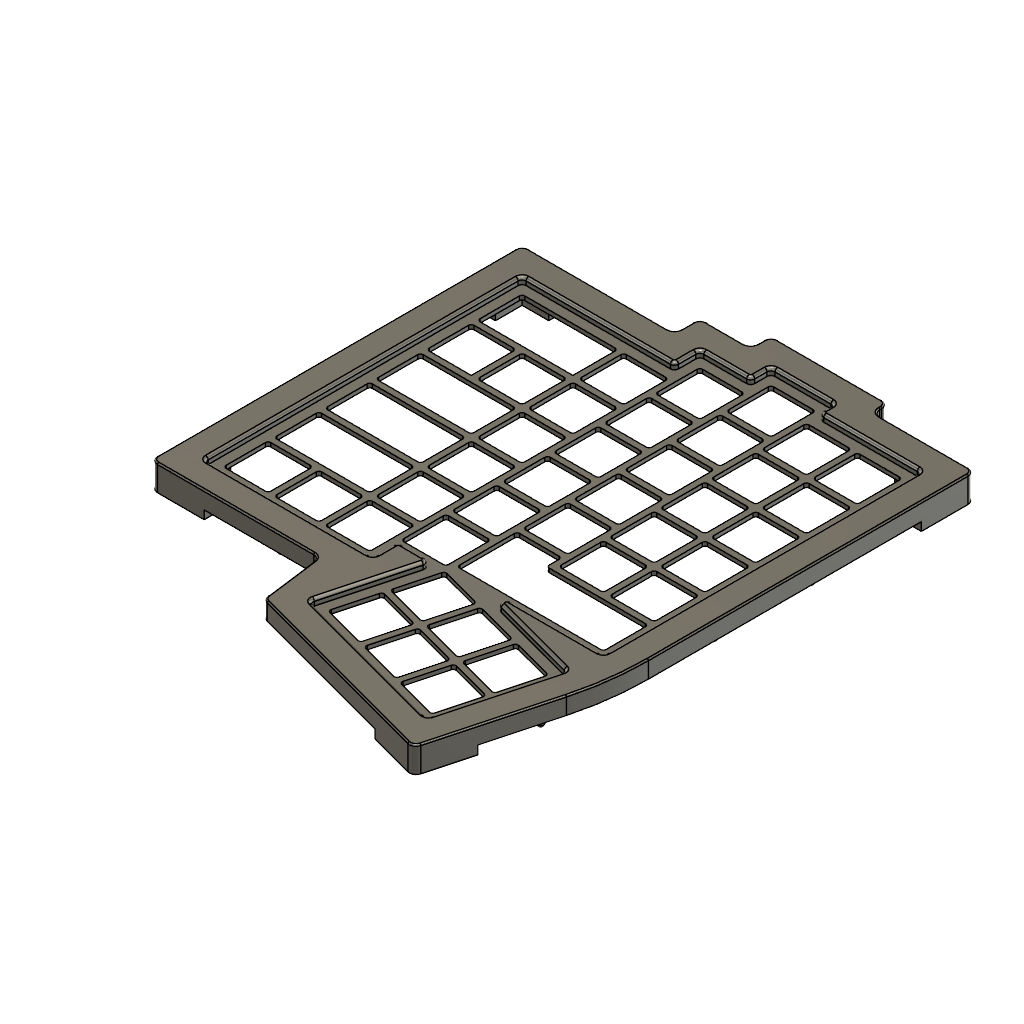
Case Top (Castor) (Autodesk Fusion 360 archive; units mm, degrees)
design "Case Top (Castor)" references "_Globals"
part number: 2026-10-17-17-44-59-793
Autodesk Fusion 360 part; units mm, degrees
(part 1 of 3)
derive "ExternalDerived1"
sketch "Sketch1" plane through (0, 0, 0) normal (0, 1, 0) x (1, 0, 0)
  line L0 (66.675, 57.15) -> (-66.675, 57.15) construction
  line L1 (-66.675, 57.15) -> (-66.675, -57.15) construction
  line L2 (-66.675, -57.15) -> (66.675, -57.15) construction
  line L3 (66.675, -57.15) -> (66.675, 57.15) construction
  line L4 (66.675, 57.15) -> (-66.675, -57.15) construction
  line L5 (-66.675, 57.15) -> (66.675, -57.15) construction
  line L6 (-66.675, 57.15) -> (-9.525, 57.15) construction
  line L7 (-9.525, 57.15) -> (-9.525, 66.675) construction
  line L8 (-9.525, 66.675) -> (9.525, 66.675) construction
  line L9 (9.525, 66.675) -> (9.525, 74.295) construction
  line L10 (9.525, 74.295) -> (28.575, 74.295) construction
  line L11 (28.575, 74.295) -> (28.575, 68.58) construction
  line L12 (28.575, 68.58) -> (66.675, 68.58) construction
  line L13 (66.675, 68.58) -> (66.675, 57.15) construction
  line L14 (-66.675, -57.15) -> (-9.525, -57.15) construction
  line L15 (-9.525, -57.15) -> (-9.525, -47.625) construction
  line L16 (-9.525, -47.625) -> (9.525, -47.625) construction
  line L17 (9.525, -47.625) -> (9.525, -45.72) construction
  line L18 (9.525, -45.72) -> (66.675, -45.72) construction
  line L19 (-66.675, -57.15) -> (-69.15, -57.15) construction
  line L20 (-69.15, -57.15) -> (-69.15, -59.625) construction
  line L21 (-66.675, 57.15) -> (-66.675, 59.625) construction
  line L22 (-66.675, 59.625) -> (-69.15, 59.625) construction
  line L23 (-9.525, 57.15) -> (-12, 57.15) construction
  line L24 (-12, 57.15) -> (-12, 59.625) construction
  line L25 (-9.525, 66.675) -> (-12, 66.675) construction
  line L26 (-12, 66.675) -> (-12, 69.15) construction
  line L27 (9.525, 66.675) -> (7.05, 66.675) construction
  line L28 (7.05, 66.675) -> (7.05, 69.15) construction
  line L29 (9.525, 74.295) -> (7.05, 74.295) construction
  line L30 (7.05, 74.295) -> (7.05, 76.77) construction
  line L31 (28.575, 74.295) -> (31.05, 74.295) construction
  line L32 (31.05, 74.295) -> (31.05, 76.77) construction
  line L33 (28.575, 68.58) -> (31.05, 68.58) construction
  line L34 (31.05, 68.58) -> (31.05, 71.055) construction
  line L35 (66.675, 68.58) -> (69.15, 68.58) construction
  line L36 (69.15, 68.58) -> (69.15, 71.055) construction
  line L37 (66.675, -45.72) -> (69.15, -45.72) construction
  line L38 (69.15, -45.72) -> (69.15, -48.195) construction
  line L39 (-9.525, -57.15) -> (-7.05, -57.15) construction
  line L40 (-7.05, -57.15) -> (-7.05, -59.625) construction
  line L41 (9.525, -47.625) -> (9.525, -47.73) construction
  line L42 (9.525, -47.73) -> (9.59, -47.73) construction
  line L43 (9.59, -47.73) -> (9.7259, -47.2229) construction
  line L44 (9.7259, -47.2229) -> (9.2188, -47.087) construction
  line L45 (9.2188, -47.087) -> (64.4214, -61.8785) construction
  line L46 (64.4214, -61.8785) -> (54.5604, -98.6803) construction
  line L47 (54.5604, -98.6803) -> (-0.6422, -83.8888) construction
  line L48 (-0.6422, -83.8888) -> (9.2188, -47.087) construction
  line L49 (-0.6422, -83.8888) -> (-1.2828, -86.2794) construction
  line L50 (-1.2828, -86.2794) -> (-3.6735, -85.6389) construction
  line L51 (54.5604, -98.6803) -> (53.9198, -101.071) construction
  line L52 (53.9198, -101.071) -> (56.3105, -101.7115) construction
  line L53 (64.4214, -61.8785) -> (65.062, -59.4879) construction
  line L54 (65.062, -59.4879) -> (67.4527, -60.1284) construction
  line L55 (-69.15, 59.625) -> (-12, 59.625)
  line L56 (-12, 59.625) -> (-12, 69.15)
  line L57 (-12, 69.15) -> (7.05, 69.15)
  line L58 (7.05, 69.15) -> (7.05, 76.77)
  line L59 (7.05, 76.77) -> (31.05, 76.77)
  line L60 (31.05, 76.77) -> (31.05, 71.055)
  line L61 (31.05, 71.055) -> (69.15, 71.055)
  line L62 (69.15, 71.055) -> (69.15, -48.195)
  line L63 (67.4527, -60.1284) -> (69.15, -48.195)
  line L64 (67.4527, -60.1284) -> (56.3105, -101.7115)
  line L65 (56.3105, -101.7115) -> (-3.6735, -85.6389)
  line L66 (-7.05, -59.625) -> (-3.6735, -85.6389)
  line L67 (-7.05, -59.625) -> (-69.15, -59.625)
  line L68 (-69.15, -59.625) -> (-69.15, 59.625)
  line L69 (-22, 79.15) -> (-2.95, 79.15)
  line L70 (-2.95, 79.15) -> (-2.95, 86.77)
  line L71 (-2.95, 86.77) -> (41.05, 86.77)
  line L72 (41.05, 86.77) -> (41.05, 81.055)
  line L73 (41.05, 81.055) -> (79.15, 81.055)
  line L74 (79.15, 81.055) -> (79.15, -48.9026)
  line L75 (77.2681, -62.1339) -> (79.15, -48.9026)
  line L76 (77.2681, -62.1339) -> (63.3816, -113.959)
  line L77 (63.3816, -113.959) -> (-12.7285, -93.5653)
  line L78 (-15.8359, -69.625) -> (-12.7285, -93.5653)
  line L79 (-15.8359, -69.625) -> (-79.15, -69.625)
  line L80 (-79.15, -69.625) -> (-79.15, 69.625)
  line L81 (-79.15, 69.625) -> (-22, 69.625)
  line L82 (-22, 69.625) -> (-22, 79.15)
  dimension "d42" = 133.35
  dimension "d43" = 114.3
  dimension "d44" = 57.15
  dimension "d45" = 9.525
  dimension "d46" = 19.05
  dimension "d47" = 7.62
  dimension "d48" = 19.05
  dimension "d49" = 5.715
  dimension "d50" = 38.1
  dimension "d51" = 57.15
  dimension "d52" = 9.525
  dimension "d53" = 19.05
  dimension "d54" = 1.905
  dimension "d55" = 2.475
  dimension "d56" = 2.475
  dimension "d57" = 2.475
  dimension "d58" = 2.475
  dimension "d59" = 2.475
  dimension "d60" = 2.475
  dimension "d61" = 2.475
  dimension "d62" = 2.475
  dimension "d63" = 2.475
  dimension "d64" = 2.475
  dimension "d65" = 2.475
  dimension "d66" = 2.475
  dimension "d67" = 2.475
  dimension "d68" = 2.475
  dimension "d69" = 2.475
  dimension "d70" = 2.475
  dimension "d71" = 2.475
  dimension "d72" = 2.475
  dimension "d73" = 2.475
  dimension "d74" = 2.475
  dimension "d75" = 2.475
  dimension "d76" = 2.475
  dimension "d77" = 0.105
  dimension "d78" = 0.065
  dimension "d79" = 0.525
  dimension "d80" = 0.525
  dimension "d81" = 57.15
  dimension "d82" = 38.1
  dimension "d83" = 2.475
  dimension "d84" = 2.475
  dimension "d85" = 2.475
  dimension "d86" = 2.475
  dimension "d87" = 2.475
  dimension "d88" = 2.475
  constraint horizontal L0
  constraint perpendicular L0 L1
  constraint parallel L0 L2
  constraint parallel L1 L3
  constraint coincident L4 origin
  constraint coincident L5 origin
  constraint perpendicular L1 L6
  constraint perpendicular L0 L7
  constraint perpendicular L7 L8
  constraint perpendicular L8 L9
  constraint perpendicular L9 L10
  constraint perpendicular L8 L11
  constraint perpendicular L9 L12
  constraint perpendicular L1 L14
  constraint perpendicular L2 L15
  constraint perpendicular L15 L16
  constraint perpendicular L2 L17
  constraint coincident L3 L18.end
  constraint perpendicular L3 L18
  constraint perpendicular L1 L19
  constraint perpendicular L19 L20
  constraint perpendicular L6 L21
  constraint perpendicular L21 L22
  constraint perpendicular L7 L23
  constraint perpendicular L23 L24
  constraint perpendicular L7 L25
  constraint perpendicular L25 L26
  constraint perpendicular L9 L27
  constraint perpendicular L27 L28
  constraint perpendicular L9 L29
  constraint perpendicular L10 L30
  constraint perpendicular L11 L31
  constraint perpendicular L10 L32
  constraint perpendicular L11 L33
  constraint perpendicular L33 L34
  constraint perpendicular L13 L35
  constraint perpendicular L12 L36
  constraint perpendicular L3 L37
  constraint perpendicular L18 L38
  constraint perpendicular L15 L39
  constraint perpendicular L39 L40
  constraint perpendicular L16 L41
  constraint perpendicular L17 L42
  constraint parallel L46 L48
  constraint parallel L45 L47
  constraint perpendicular L47 L48
  constraint collinear L44 L45
  constraint perpendicular L43 L44
  constraint perpendicular L47 L49
  constraint perpendicular L48 L50
  constraint perpendicular L47 L51
  constraint perpendicular L51 L52
  constraint perpendicular L45 L53
  constraint perpendicular L53 L54
  measures "d42" distance of L1.end L2.end
  measures "d43" distance of L0.end L1.end
  measures "d44" distance of L0.end L6.end
  measures "d45" distance of L6.end L7.end
  measures "d46" distance of L7.end L8.end
  measures "d47" distance of L8.end L9.end
  measures "d48" distance of L9.end L10.end
  measures "d49" distance of L10.end L11.end
  measures "d50" distance of L11.end L12.end
  measures "d51" distance of L1.end L14.end
  measures "d52" distance of L14.end L15.end
  measures "d53" distance of L15.end L16.end
  measures "d54" distance of L16.end L17.end
  measures "d55" distance of L1.end L19.end
  measures "d56" distance of L19.end L20.end
  measures "d57" distance of L0.end L21.end
  measures "d58" distance of L21.end L22.end
  measures "d59" distance of L6.end L23.end
  measures "d60" distance of L23.end L24.end
  measures "d61" distance of L7.end L25.end
  measures "d62" distance of L25.end L26.end
  measures "d63" distance of L8.end L27.end
  measures "d64" distance of L27.end L28.end
  measures "d65" distance of L9.end L29.end
  measures "d66" distance of L29.end L30.end
  measures "d67" distance of L10.end L31.end
  measures "d68" distance of L31.end L32.end
  measures "d69" distance of L11.end L33.end
  measures "d70" distance of L33.end L34.end
  measures "d71" distance of L12.end L35.end
  measures "d72" distance of L35.end L36.end
  measures "d73" distance of L18.end L37.end
  measures "d74" distance of L37.end L38.end
  measures "d75" distance of L14.end L39.end
  measures "d76" distance of L39.end L40.end
  measures "d77" distance of L16.end L41.end
  measures "d78" distance of L41.end L42.end
  measures "d79" distance of L42.end L43.end
  measures "d80" distance of L43.end L44.end
  measures "d81" distance of L44.end L45.end
  measures "d82" distance of L44.end L47.end
  measures "d83" distance of L47.end L49.end
  measures "d84" distance of L49.end L50.end
  measures "d85" distance of L46.end L51.end
  measures "d86" distance of L51.end L52.end
  measures "d87" distance of L45.end L53.end
  measures "d88" distance of L53.end L54.end
extrude "Extrude1" add sketch "Sketch1" against normal blind 1.5 contours L55 L56 L57 L58 L59 L60 L61 L62 L63 L64 L65 L66 L67 L68
extrude "Extrude2" add sketch "Sketch1" against normal blind 4
sketch "Sketch2" plane through (0, 0, 0) normal (0, 1, 0) x (-1, 0, 0)
  line L0 (15.8359, 69.625) -> (12.7285, 93.5653)
  line L1 (12.7285, 93.5653) -> (-63.3816, 113.959)
  line L2 (-63.3816, 113.959) -> (-77.2681, 62.1339)
  line L3 (-77.2681, 62.1339) -> (-79.15, 48.9026)
  line L4 (-79.15, 48.9026) -> (-79.15, -81.055)
  line L5 (-79.15, -81.055) -> (-41.05, -81.055)
  line L6 (-41.05, -81.055) -> (-41.05, -86.77)
  line L7 (-41.05, -86.77) -> (2.95, -86.77)
  line L8 (2.95, -86.77) -> (2.95, -79.15)
  line L9 (2.95, -79.15) -> (22, -79.15)
  line L10 (22, -79.15) -> (22, -69.625)
  line L11 (22, -69.625) -> (79.15, -69.625)
  line L12 (79.15, -69.625) -> (79.15, 69.625)
  line L13 (79.15, 69.625) -> (15.8359, 69.625)
  line L14 (79.15, -69.625) -> (79.15, -57.15) construction
  line L15 (79.15, -57.15) -> (66.675, -57.15) construction
  line L16 (66.675, -57.15) -> (47.625, -57.15) construction
  line L17 (47.625, -57.15) -> (9.525, -57.15) construction
  line L18 (9.525, -57.15) -> (9.525, -66.675) construction
  line L19 (9.525, -66.675) -> (-9.525, -66.675) construction
  line L20 (-9.525, -66.675) -> (-9.525, -74.295) construction
  line L21 (-9.525, -74.295) -> (-28.575, -74.295) construction
  line L22 (-28.575, -74.295) -> (-28.575, -68.58) construction
  line L23 (-28.575, -68.58) -> (-47.625, -68.58) construction
  line L24 (-47.625, -68.58) -> (-66.675, -68.58) construction
  line L25 (-66.675, -68.58) -> (-66.675, 26.67) construction
  line L26 (-66.675, 26.67) -> (-28.575, 26.67) construction
  line L27 (-28.575, 26.67) -> (-28.575, -68.58) construction
  line L28 (-47.625, -68.58) -> (-47.625, -49.53) construction
  line L29 (-47.625, -49.53) -> (-28.575, -49.53) construction
  line L30 (-28.575, -68.58) -> (-47.625, -49.53) construction
  line L31 (-47.625, -68.58) -> (-28.575, -49.53) construction
  line L32 (-9.525, -66.675) -> (-9.525, -55.245) construction
  line L33 (-9.525, -55.245) -> (-28.575, -55.245) construction
  line L34 (9.525, -57.15) -> (9.525, -47.625) construction
  line L35 (9.525, -47.625) -> (-9.525, -47.625) construction
  line L36 (-9.525, -55.245) -> (-9.525, 20.955) construction
  line L37 (-9.525, 20.955) -> (-28.575, 20.955) construction
  line L38 (9.525, -47.625) -> (9.525, 47.625) construction
  line L39 (9.525, 47.625) -> (-9.525, 47.625) construction
  line L40 (-9.525, 47.625) -> (-9.525, 20.955) construction
  line L41 (66.675, -57.15) -> (66.675, -38.1) construction
  line L42 (66.675, -38.1) -> (66.675, -19.05) construction
  line L43 (66.675, -19.05) -> (66.675, 38.1) construction
  line L44 (66.675, 38.1) -> (66.675, 57.15) construction
  line L45 (66.675, 57.15) -> (47.625, 57.15) construction
  line L46 (47.625, 57.15) -> (9.525, 57.15) construction
  line L47 (9.525, 57.15) -> (9.525, 47.625) construction
  line L48 (66.675, 38.1) -> (47.625, 38.1) construction
  line L49 (47.625, 38.1) -> (9.525, 38.1) construction
  line L50 (47.625, 38.1) -> (47.625, 57.15) construction
  line L51 (28.575, -57.15) -> (28.575, -38.1) construction
  line L52 (28.575, -38.1) -> (47.625, -38.1) construction
  line L53 (47.625, -38.1) -> (66.675, -38.1) construction
  line L54 (47.625, -38.1) -> (47.625, -19.05) construction
  line L55 (47.625, -19.05) -> (66.675, -19.05) construction
  line L56 (28.575, -38.1) -> (28.575, 38.1) construction
  line L57 (28.575, -38.1) -> (9.525, -38.1) construction
  line L58 (47.625, -19.05) -> (28.575, -19.05) construction
  line L59 (66.675, -57.15) -> (28.575, -38.1) construction
  line L60 (28.575, -57.15) -> (66.675, -38.1) construction
  line L61 (66.675, -38.1) -> (47.625, -19.05) construction
  line L62 (47.625, -38.1) -> (66.675, -19.05) construction
  line L63 (9.525, -66.675) -> (-9.525, -47.625) construction
  line L64 (-9.525, -66.675) -> (9.525, -47.625) construction
  line L65 (-9.525, -74.295) -> (-28.575, -55.245) construction
  line L66 (-28.575, -74.295) -> (-9.525, -55.245) construction
  line L67 (-66.675, 26.67) -> (-66.675, 45.72) construction
  line L68 (-66.675, 45.72) -> (-9.525, 45.72) construction
  line L69 (-9.525, 45.72) -> (-66.675, 26.67) construction
  line L70 (-28.575, 26.67) -> (-9.525, 26.67) construction
  line L71 (-66.675, 45.72) -> (-9.525, 26.67) construction
  line L72 (66.675, 38.1) -> (47.625, 57.15) construction
  line L73 (47.625, 38.1) -> (66.675, 57.15) construction
  line L74 (-9.525, 47.625) -> (-9.525, 47.73) construction
  line L75 (-9.525, 47.73) -> (-9.59, 47.73) construction
  line L76 (-9.59, 47.73) -> (-9.7259, 47.2229) construction
  line L77 (-9.7259, 47.2229) -> (-9.2188, 47.087) construction
  line L78 (-9.2188, 47.087) -> (-4.2883, 65.4879) construction
  line L79 (-4.2883, 65.4879) -> (-22.6892, 70.4184) construction
  line L80 (-22.6892, 70.4184) -> (-27.6197, 52.0175) construction
  line L81 (-27.6197, 52.0175) -> (-9.2188, 47.087) construction
  line L82 (-9.2188, 47.087) -> (-22.6892, 70.4184) construction
  line L83 (-27.6197, 52.0175) -> (-4.2883, 65.4879) construction
  line L84 (-4.2883, 65.4879) -> (0.6422, 83.8888) construction
  line L85 (0.6422, 83.8888) -> (-54.5604, 98.6803) construction
  line L86 (-54.5604, 98.6803) -> (-64.4214, 61.8785) construction
  line L87 (-64.4214, 61.8785) -> (-27.6197, 52.0175) construction
  line L88 (-26.206, 52.8216) -> (-10.0229, 48.5007)
  line L89 (-10.0229, 48.5007) -> (-5.702, 64.6838)
  line L90 (-5.702, 64.6838) -> (-21.885, 69.0047)
  line L91 (-21.885, 69.0047) -> (-26.206, 52.8216)
  line L92 (-26.206, 52.8216) -> (-5.702, 64.6838) construction
  line L93 (-10.0229, 48.5007) -> (-21.885, 69.0047) construction
  line L94 (-28.4238, 53.4312) -> (-24.1028, 69.6143)
  line L95 (-24.1028, 69.6143) -> (-40.2859, 73.9352)
  line L96 (-40.2859, 73.9352) -> (-44.6069, 57.7521)
  line L97 (-44.6069, 57.7521) -> (-28.4238, 53.4312)
  line L98 (-46.8247, 58.3617) -> (-42.5037, 74.5448)
  line L99 (-42.5037, 74.5448) -> (-58.6868, 78.8657)
  line L100 (-58.6868, 78.8657) -> (-63.0077, 62.6826)
  line L101 (-63.0077, 62.6826) -> (-46.8247, 58.3617)
  line L102 (-5.0924, 66.9016) -> (-0.7715, 83.0847)
  line L103 (-0.7715, 83.0847) -> (-16.9545, 87.4056)
  line L104 (-16.9545, 87.4056) -> (-21.2755, 71.2225)
  line L105 (-21.2755, 71.2225) -> (-5.0924, 66.9016)
  line L106 (-23.4933, 71.8321) -> (-19.1723, 88.0152)
  line L107 (-19.1723, 88.0152) -> (-35.3554, 92.3361)
  line L108 (-35.3554, 92.3361) -> (-39.6764, 76.153)
  line L109 (-39.6764, 76.153) -> (-23.4933, 71.8321)
  line L110 (-41.8942, 76.7626) -> (-37.5732, 92.9457)
  line L111 (-37.5732, 92.9457) -> (-53.7563, 97.2666)
  line L112 (-53.7563, 97.2666) -> (-58.0772, 81.0835)
  line L113 (-58.0772, 81.0835) -> (-41.8942, 76.7626)
  line L114 (48.775, 39.25) -> (65.525, 39.25)
  line L115 (65.525, 39.25) -> (65.525, 56)
  line L116 (65.525, 56) -> (48.775, 56)
  line L117 (48.775, 56) -> (48.775, 39.25)
  line L118 (48.775, 39.25) -> (65.525, 56) construction
  line L119 (65.525, 39.25) -> (48.775, 56) construction
  line L120 (48.775, -36.95) -> (65.525, -36.95)
  line L121 (65.525, -36.95) -> (65.525, -20.2)
  line L122 (65.525, -20.2) -> (48.775, -20.2)
  line L123 (48.775, -20.2) -> (48.775, -36.95)
  line L124 (48.775, -36.95) -> (65.525, -20.2) construction
  line L125 (65.525, -36.95) -> (48.775, -20.2) construction
  line L126 (-8.375, -65.525) -> (8.375, -65.525)
  line L127 (8.375, -65.525) -> (8.375, -48.775)
  line L128 (8.375, -48.775) -> (-8.375, -48.775)
  line L129 (-8.375, -48.775) -> (-8.375, -65.525)
  line L130 (-8.375, -65.525) -> (8.375, -48.775) construction
  line L131 (8.375, -65.525) -> (-8.375, -48.775) construction
  line L132 (-27.425, -73.145) -> (-10.675, -73.145)
  line L133 (-10.675, -73.145) -> (-10.675, -56.395)
  line L134 (-10.675, -56.395) -> (-27.425, -56.395)
  line L135 (-27.425, -56.395) -> (-27.425, -73.145)
  line L136 (-27.425, -73.145) -> (-10.675, -56.395) construction
  line L137 (-10.675, -73.145) -> (-27.425, -56.395) construction
  line L138 (-46.475, -67.43) -> (-29.725, -67.43)
  line L139 (-29.725, -67.43) -> (-29.725, -50.68)
  line L140 (-29.725, -50.68) -> (-46.475, -50.68)
  line L141 (-46.475, -50.68) -> (-46.475, -67.43)
  line L142 (-46.475, -67.43) -> (-29.725, -50.68) construction
  line L143 (-29.725, -67.43) -> (-46.475, -50.68) construction
  line L144 (29.725, -56) -> (65.525, -56)
  line L145 (65.525, -56) -> (65.525, -39.25)
  line L146 (65.525, -39.25) -> (29.725, -39.25)
  line L147 (29.725, -39.25) -> (29.725, -56)
  line L148 (29.725, -56) -> (65.525, -39.25) construction
  line L149 (65.525, -56) -> (29.725, -39.25) construction
  line L150 (-65.525, 27.82) -> (-10.675, 27.82)
  line L151 (-10.675, 27.82) -> (-10.675, 44.57)
  line L152 (-10.675, 44.57) -> (-65.525, 44.57)
  line L153 (-65.525, 44.57) -> (-65.525, 27.82)
  line L154 (-65.525, 27.82) -> (-10.675, 44.57) construction
  line L155 (-10.675, 27.82) -> (-65.525, 44.57) construction
  line L156 (-10.675, 27.82) -> (-27.425, 27.82)
  line L157 (-27.425, 27.82) -> (-27.425, 22.105)
  line L158 (-27.425, 22.105) -> (-10.675, 22.105)
  line L159 (-10.675, 22.105) -> (-10.675, 27.82)
  line L160 (46.475, 39.25) -> (46.475, 56)
  line L161 (46.475, 56) -> (29.725, 56)
  line L162 (29.725, 56) -> (29.725, 39.25)
  line L163 (29.725, 39.25) -> (46.475, 39.25)
  line L164 (27.425, 39.25) -> (27.425, 56)
  line L165 (27.425, 56) -> (10.675, 56)
  line L166 (10.675, 56) -> (10.675, 39.25)
  line L167 (10.675, 39.25) -> (27.425, 39.25)
  line L168 (46.475, -36.95) -> (46.475, -20.2)
  line L169 (46.475, -20.2) -> (29.725, -20.2)
  line L170 (29.725, -20.2) -> (29.725, -36.95)
  line L171 (29.725, -36.95) -> (46.475, -36.95)
  line L172 (28.575, -57.15) -> (9.525, -38.1) construction
  line L173 (28.575, -38.1) -> (9.525, -57.15) construction
  line L174 (10.675, -56) -> (27.425, -56)
  line L175 (27.425, -56) -> (27.425, -39.25)
  line L176 (27.425, -39.25) -> (10.675, -39.25)
  line L177 (10.675, -39.25) -> (10.675, -56)
  line L178 (10.675, -56) -> (27.425, -39.25) construction
  line L179 (27.425, -56) -> (10.675, -39.25) construction
  line L180 (10.675, -36.95) -> (27.425, -36.95)
  line L181 (27.425, -36.95) -> (27.425, -20.2)
  line L182 (27.425, -20.2) -> (10.675, -20.2)
  line L183 (10.675, -20.2) -> (10.675, -36.95)
  line L184 (10.675, -17.9) -> (27.425, -17.9)
  line L185 (27.425, -17.9) -> (27.425, -1.15)
  line L186 (27.425, -1.15) -> (10.675, -1.15)
  line L187 (10.675, -1.15) -> (10.675, -17.9)
  line L188 (10.675, 1.15) -> (27.425, 1.15)
  line L189 (27.425, 1.15) -> (27.425, 17.9)
  line L190 (27.425, 17.9) -> (10.675, 17.9)
  line L191 (10.675, 17.9) -> (10.675, 1.15)
  line L192 (10.675, 20.2) -> (27.425, 20.2)
  line L193 (27.425, 20.2) -> (27.425, 36.95)
  line L194 (27.425, 36.95) -> (10.675, 36.95)
  line L195 (10.675, 36.95) -> (10.675, 20.2)
  line L196 (8.375, -46.475) -> (8.375, -29.725)
  line L197 (8.375, -29.725) -> (-8.375, -29.725)
  line L198 (-8.375, -29.725) -> (-8.375, -46.475)
  line L199 (-8.375, -46.475) -> (8.375, -46.475)
  line L200 (8.375, -27.425) -> (8.375, -10.675)
  line L201 (8.375, -10.675) -> (-8.375, -10.675)
  line L202 (-8.375, -10.675) -> (-8.375, -27.425)
  line L203 (-8.375, -27.425) -> (8.375, -27.425)
  line L204 (8.375, -8.375) -> (8.375, 8.375)
  line L205 (8.375, 8.375) -> (-8.375, 8.375)
  line L206 (-8.375, 8.375) -> (-8.375, -8.375)
  line L207 (-8.375, -8.375) -> (8.375, -8.375)
  line L208 (8.375, 10.675) -> (8.375, 27.425)
  line L209 (8.375, 27.425) -> (-8.375, 27.425)
  line L210 (-8.375, 27.425) -> (-8.375, 10.675)
  line L211 (-8.375, 10.675) -> (8.375, 10.675)
  line L212 (8.375, 29.725) -> (8.375, 46.475)
  line L213 (8.375, 46.475) -> (-8.375, 46.475)
  line L214 (-8.375, 46.475) -> (-8.375, 29.725)
  line L215 (-8.375, 29.725) -> (8.375, 29.725)
  line L216 (-10.675, -54.095) -> (-10.675, -37.345)
  line L217 (-10.675, -37.345) -> (-27.425, -37.345)
  line L218 (-27.425, -37.345) -> (-27.425, -54.095)
  line L219 (-27.425, -54.095) -> (-10.675, -54.095)
  line L220 (-10.675, -35.045) -> (-10.675, -18.295)
  line L221 (-10.675, -18.295) -> (-27.425, -18.295)
  line L222 (-27.425, -18.295) -> (-27.425, -35.045)
  line L223 (-27.425, -35.045) -> (-10.675, -35.045)
  line L224 (-10.675, -15.995) -> (-10.675, 0.755)
  line L225 (-10.675, 0.755) -> (-27.425, 0.755)
  line L226 (-27.425, 0.755) -> (-27.425, -15.995)
  line L227 (-27.425, -15.995) -> (-10.675, -15.995)
  line L228 (-10.675, 3.055) -> (-10.675, 19.805)
  line L229 (-10.675, 19.805) -> (-27.425, 19.805)
  line L230 (-27.425, 19.805) -> (-27.425, 3.055)
  line L231 (-27.425, 3.055) -> (-10.675, 3.055)
  line L232 (-48.775, -67.43) -> (-48.775, -50.68)
  line L233 (-48.775, -50.68) -> (-65.525, -50.68)
  line L234 (-65.525, -50.68) -> (-65.525, -67.43)
  line L235 (-65.525, -67.43) -> (-48.775, -67.43)
  line L236 (-29.725, -48.38) -> (-29.725, -31.63)
  line L237 (-29.725, -31.63) -> (-46.475, -31.63)
  line L238 (-46.475, -31.63) -> (-46.475, -48.38)
  line L239 (-46.475, -48.38) -> (-29.725, -48.38)
  line L240 (-48.775, -48.38) -> (-48.775, -31.63)
  line L241 (-48.775, -31.63) -> (-65.525, -31.63)
  line L242 (-65.525, -31.63) -> (-65.525, -48.38)
  line L243 (-65.525, -48.38) -> (-48.775, -48.38)
  line L244 (-29.725, -29.33) -> (-29.725, -12.58)
  line L245 (-29.725, -12.58) -> (-46.475, -12.58)
  line L246 (-46.475, -12.58) -> (-46.475, -29.33)
  line L247 (-46.475, -29.33) -> (-29.725, -29.33)
  line L248 (-48.775, -29.33) -> (-48.775, -12.58)
  line L249 (-48.775, -12.58) -> (-65.525, -12.58)
  line L250 (-65.525, -12.58) -> (-65.525, -29.33)
  line L251 (-65.525, -29.33) -> (-48.775, -29.33)
  line L252 (-29.725, -10.28) -> (-29.725, 6.47)
  line L253 (-29.725, 6.47) -> (-46.475, 6.47)
  line L254 (-46.475, 6.47) -> (-46.475, -10.28)
  line L255 (-46.475, -10.28) -> (-29.725, -10.28)
  line L256 (-48.775, -10.28) -> (-48.775, 6.47)
  line L257 (-48.775, 6.47) -> (-65.525, 6.47)
  line L258 (-65.525, 6.47) -> (-65.525, -10.28)
  line L259 (-65.525, -10.28) -> (-48.775, -10.28)
  line L260 (-29.725, 8.77) -> (-29.725, 25.52)
  line L261 (-29.725, 25.52) -> (-46.475, 25.52)
  line L262 (-46.475, 25.52) -> (-46.475, 8.77)
  line L263 (-46.475, 8.77) -> (-29.725, 8.77)
  line L264 (-48.775, 8.77) -> (-48.775, 25.52)
  line L265 (-48.775, 25.52) -> (-65.525, 25.52)
  line L266 (-65.525, 25.52) -> (-65.525, 8.77)
  line L267 (-65.525, 8.77) -> (-48.775, 8.77)
  line L268 (29.725, -17.9) -> (65.525, -17.9)
  line L269 (65.525, -17.9) -> (65.525, -1.15)
  line L270 (65.525, -1.15) -> (29.725, -1.15)
  line L271 (29.725, -1.15) -> (29.725, -17.9)
  line L272 (29.725, 1.15) -> (65.525, 1.15)
  line L273 (65.525, 1.15) -> (65.525, 17.9)
  line L274 (65.525, 17.9) -> (29.725, 17.9)
  line L275 (29.725, 17.9) -> (29.725, 1.15)
  line L276 (29.725, 20.2) -> (65.525, 20.2)
  line L277 (65.525, 20.2) -> (65.525, 36.95)
  line L278 (65.525, 36.95) -> (29.725, 36.95)
  line L279 (29.725, 36.95) -> (29.725, 20.2)
  point P0 (-15.954, 58.7527)
  point P1 (57.15, 47.625)
  point P2 (57.15, -28.575)
  point P3 (0, -57.15)
  point P4 (-19.05, -64.77)
  point P5 (-38.1, -59.055)
  point P6 (47.625, -47.625)
  point P7 (-38.1, 36.195)
  point P8 (19.05, -47.625)
  dimension "d95" = 12.475
  dimension "d96" = 12.475
  dimension "d97" = 19.05
  dimension "d98" = 38.1
  dimension "d99" = 9.525
  dimension "d100" = 19.05
  dimension "d101" = 7.62
  dimension "d102" = 19.05
  dimension "d103" = 5.715
  dimension "d104" = 19.05
  dimension "d105" = 19.05
  dimension "d106" = 95.25
  dimension "d107" = 38.1
  dimension "d108" = 19.05
  dimension "d109" = 11.43
  dimension "d110" = 9.525
  dimension "d111" = 19.05
  dimension "d112" = 76.2
  dimension "d113" = 95.25
  dimension "d114" = 19.05
  dimension "d115" = 19.05
  dimension "d116" = 19.05
  dimension "d117" = 57.15
  dimension "d118" = 19.05
  dimension "d119" = 19.05
  dimension "d120" = 38.1
  dimension "d121" = 19.05
  dimension "d122" = 19.05
  dimension "d123" = 19.05
  dimension "d124" = 19.05
  dimension "d125" = 19.05
  dimension "d126" = 0.105
  dimension "d127" = 0.065
  dimension "d128" = 0.525
  dimension "d129" = 0.525
  dimension "d130" = 19.05
  dimension "d131" = 19.05
  dimension "d132" = 19.05
  dimension "d133" = 19.05
  dimension "d134" = 57.15
  dimension "d135" = 38.1
  dimension "d136" = 16.75
  dimension "d137" = 16.75
  dimension "d141" = 19.05
  dimension "d142" = 16.75
  dimension "d143" = 16.75
  dimension "d144" = 16.75
  dimension "d145" = 16.75
  dimension "d146" = 16.75
  dimension "d147" = 16.75
  dimension "d148" = 16.75
  dimension "d149" = 16.75
  dimension "d150" = 16.75
  dimension "d151" = 16.75
  dimension "d152" = 35.8
  dimension "d153" = 16.75
  dimension "d154" = 54.85
  dimension "d155" = 16.75
  dimension "d156" = 16.75
  dimension "d157" = 5.715
  dimension "d161" = 0
  dimension "d165" = 0
  dimension "d166" = 16.75
  dimension "d167" = 16.75
  dimension "d170" = 0
  dimension "d171" = 19.05
  dimension "d174" = 0
  dimension "d175" = 19.05
  dimension "d178" = 0
  dimension "d179" = 19.05
  dimension "d183" = 19.05
  dimension "d186" = 0
  dimension "d187" = 38.1
  dimension "d190" = 0
  dimension "d191" = 19.05
  constraint coincident L11.end L12.start
  constraint perpendicular L11 L14
  constraint perpendicular L12 L15
  constraint parallel L15 L16
  constraint parallel L15 L17
  constraint perpendicular L17 L18
  constraint perpendicular L18 L19
  constraint perpendicular L17 L20
  constraint perpendicular L20 L21
  constraint perpendicular L17 L22
  constraint perpendicular L22 L23
  constraint parallel L17 L24
  constraint perpendicular L17 L25
  constraint perpendicular L25 L26
  constraint perpendicular L24 L28
  constraint coincident L27 L29.end
  constraint perpendicular L27 L29
  constraint perpendicular L19 L32
  constraint coincident L27 L33.end
  constraint perpendicular L27 L33
  constraint perpendicular L17 L34
  constraint perpendicular L18 L35
  constraint perpendicular L33 L36
  constraint coincident L27 L37.end
  constraint perpendicular L27 L37
  constraint perpendicular L35 L38
  constraint perpendicular L38 L39
  constraint perpendicular L15 L41
  constraint perpendicular L15 L42
  constraint perpendicular L15 L43
  constraint perpendicular L15 L44
  constraint perpendicular L44 L45
  constraint perpendicular L44 L46
  constraint perpendicular L44 L48
  constraint coincident L38 L49.end
  constraint perpendicular L38 L49
  constraint midpoint L17 L51.start
  constraint perpendicular L17 L51
  constraint perpendicular L51 L52
  constraint perpendicular L53 L54
  constraint midpoint L49 L56.end
  constraint coincident L38 L57.end
  constraint perpendicular L38 L57
  constraint coincident L56 L58.end
  constraint perpendicular L56 L58
  constraint perpendicular L26 L67
  constraint coincident L40 L68.end
  constraint perpendicular L40 L68
  constraint coincident L40 L70.end
  constraint perpendicular L40 L70
  constraint perpendicular L39 L74
  constraint perpendicular L76 L77
  constraint perpendicular L74 L75
  constraint collinear L77 L81
  constraint parallel L78 L80
  constraint perpendicular L79 L80
  constraint perpendicular L79 L84
  constraint perpendicular L84 L85
  constraint perpendicular L79 L86
  constraint perpendicular L88 L89
  constraint parallel L88 L90
  constraint parallel L89 L91
  constraint coincident L92 P0
  constraint coincident L93 P0
  constraint midpoint L82 P0
  constraint horizontal L114
  constraint perpendicular L114 L115
  constraint parallel L114 L116
  constraint parallel L115 L117
  constraint coincident L118 P1
  constraint coincident L119 P1
  constraint midpoint L73 P1
  constraint horizontal L120
  constraint perpendicular L120 L121
  constraint parallel L120 L122
  constraint parallel L121 L123
  constraint coincident L124 P2
  constraint coincident L125 P2
  constraint midpoint L61 P2
  constraint horizontal L126
  constraint perpendicular L126 L127
  constraint parallel L126 L128
  constraint parallel L127 L129
  constraint coincident L130 P3
  constraint coincident L131 P3
  constraint midpoint L64 P3
  constraint horizontal L132
  constraint perpendicular L132 L133
  constraint parallel L132 L134
  constraint parallel L133 L135
  constraint coincident L136 P4
  constraint coincident L137 P4
  constraint midpoint L65 P4
  constraint horizontal L138
  constraint perpendicular L138 L139
  constraint parallel L138 L140
  constraint parallel L139 L141
  constraint coincident L142 P5
  constraint coincident L143 P5
  constraint midpoint L30 P5
  constraint horizontal L144
  constraint perpendicular L144 L145
  constraint parallel L144 L146
  constraint parallel L145 L147
  constraint coincident L148 P6
  constraint coincident L149 P6
  constraint midpoint L59 P6
  constraint horizontal L150
  constraint perpendicular L150 L151
  constraint parallel L150 L152
  constraint parallel L151 L153
  constraint coincident L154 P7
  constraint coincident L155 P7
  constraint midpoint L69 P7
  constraint horizontal L156
  constraint vertical L157
  constraint horizontal L158
  constraint vertical L159
  constraint horizontal L174
  constraint perpendicular L174 L175
  constraint parallel L174 L176
  constraint parallel L175 L177
  constraint coincident L178 P8
  constraint coincident L179 P8
  constraint midpoint L173 P8
  measures "d95" distance of L11.end L14.end
  measures "d96" distance of L14.end L15.end
  measures "d97" distance of L15.end L16.end
  measures "d98" distance of L16.end L17.end
  measures "d99" distance of L17.end L18.end
  measures "d100" distance of L18.end L19.end
  measures "d101" distance of L19.end L20.end
  measures "d102" distance of L20.end L21.end
  measures "d103" distance of L21.end L22.end
  measures "d104" distance of L22.end L23.end
  measures "d105" distance of L23.end L24.end
  measures "d106" distance of L24.end L25.end
  measures "d107" distance of L25.end L26.end
  measures "d108" distance of L23.end L28.end
  measures "d109" distance of L19.end L32.end
  measures "d110" distance of L17.end L34.end
  measures "d111" distance of L34.end L35.end
  measures "d112" distance of L32.end L36.end
  measures "d113" distance of L34.end L38.end
  measures "d114" distance of L38.end L39.end
  measures "d115" distance of L15.end L41.end
  measures "d116" distance of L41.end L42.end
  measures "d117" distance of L42.end L43.end
  measures "d118" distance of L43.end L44.end
  measures "d119" distance of L44.end L45.end
  measures "d120" distance of L45.end L46.end
  measures "d121" distance of L43.end L48.end
  measures "d122" distance of L51.start L51.end
  measures "d123" distance of L51.end L52.end
  measures "d124" distance of L52.end L54.end
  measures "d125" distance of L25.end L67.end
  measures "d126" distance of L39.end L74.end
  measures "d127" distance of L74.end L75.end
  measures "d128" distance of L75.end L76.end
  measures "d129" distance of L76.end L77.end
  measures "d130" distance of L77.end L78.end
  measures "d131" distance of L78.end L79.end
  measures "d132" distance of L79.end L80.end
  measures "d133" distance of L78.end L84.end
  measures "d134" distance of L84.end L85.end
  measures "d135" distance of L85.end L86.end
  measures "d136" distance of L89.end L90.end
  measures "d137" distance of L88.end L89.end
  measures "d142" distance of L115.end L116.end
  measures "d143" distance of L114.end L115.end
  measures "d144" distance of L121.end L122.end
  measures "d145" distance of L120.end L121.end
  measures "d146" distance of L127.end L128.end
  measures "d147" distance of L126.end L127.end
  measures "d148" distance of L133.end L134.end
  measures "d149" distance of L132.end L133.end
  measures "d150" distance of L139.end L140.end
  measures "d151" distance of L138.end L139.end
  measures "d152" distance of L145.end L146.end
  measures "d153" distance of L144.end L145.end
  measures "d154" distance of L151.end L152.end
  measures "d155" distance of L150.end L151.end
  measures "d156" distance of L150.end L156.end
  measures "d157" distance of L150.end L158.end
  measures "d166" distance of L175.end L176.end
  measures "d167" distance of L174.end L175.end
extrude "Extrude3" cut sketch "Sketch2" against normal through all contours L88 L89 L90 L91 | L94 L95 L96 L97 | L98 L99 L100 L101 | L102 L103 L104 L105 | L106 L107 L108 L109 | L110 L111 L112 L113 | L114 L115 L116 L117 | L120 L121 L122 L123 | L126 L127 L128 L129 | L132 L133 L134 L135 | L138 L139 L140 L141 | L144 L145 L146 L147 | L150 L151 L152 L153 L156 | L150 L156 L157 L158 L159 | L160 L161 L162 L163 | L164 L165 L166 L167 | L168 L169 L170 L171 | L174 L175 L176 L177 | L180 L181 L182 L183 | L184 L185 L186 L187 | L188 L189 L190 L191 | L192 L193 L194 L195 | L196 L197 L198 L199 | L200 L201 L202 L203 | L204 L205 L206 L207 | L208 L209 L210 L211 | L212 L213 L214 L215 | L216 L217 L218 L219 | L220 L221 L222 L223 | L224 L225 L226 L227 | L228 L229 L230 L231 | L232 L233 L234 L235 | L236 L237 L238 L239 | L240 L241 L242 L243 | L244 L245 L246 L247 | L248 L249 L250 L251 | L252 L253 L254 L255 | L256 L257 L258 L259 | L260 L261 L262 L263 | L264 L265 L266 L267 | L268 L269 L270 L271 | L272 L273 L274 L275 | L276 L277 L278 L279
fillet "Fillet1" radius 1 168 edges at (-65.525, -0.75, 39.25) (-46.475, -0.75, 39.25) (-27.425, -0.75, 39.25) (-27.425, -0.75, 20.2) (-65.525, -0.75, 20.2) (-65.525, -0.75, 1.15) (-27.425, -0.75, 1.15) (-27.425, -0.75, -17.9) (-65.525, -0.75, -17.9) (-65.525, -0.75, -36.95) (-46.475, -0.75, -36.95) (-27.425, -0.75, -36.95) (-27.425, -0.75, -56) (-65.525, -0.75, -56) (-8.375, -0.75, -65.525) (-8.375, -0.75, -46.475) (-8.375, -0.75, -27.425) (-8.375, -0.75, -8.375) (-8.375, -0.75, 10.675) (-8.375, -0.75, 29.725) (10.675, -0.75, 22.105) (27.425, -0.75, 27.82) (48.775, -0.75, 8.77) (29.725, -0.75, 8.77) (10.675, -0.75, 3.055) (10.675, -0.75, -15.995) (29.725, -0.75, -10.28) (48.775, -0.75, -10.28) (48.775, -0.75, -29.33) (29.725, -0.75, -29.33) (10.675, -0.75, -35.045) (10.675, -0.75, -54.095) (10.675, -0.75, -73.145) (29.725, -0.75, -67.43) (29.725, -0.75, -48.38) (48.775, -0.75, -48.38) (48.775, -0.75, -67.43) (10.0229, -0.75, 48.5007) (5.0924, -0.75, 66.9016) (23.4933, -0.75, 71.8321) (28.4238, -0.75, 53.4312) (46.8247, -0.75, 58.3617) (41.8942, -0.75, 76.7626) (63.0077, -0.75, 62.6826) (58.0772, -0.75, 81.0835) (44.6069, -0.75, 57.7521) (39.6764, -0.75, 76.153) (26.206, -0.75, 52.8216) (21.2755, -0.75, 71.2225) (53.7563, -0.75, 97.2666) (58.6868, -0.75, 78.8657) (40.2859, -0.75, 73.9352) (35.3554, -0.75, 92.3361) (16.9545, -0.75, 87.4056) (21.885, -0.75, 69.0047) (0.7715, -0.75, 83.0847) (5.702, -0.75, 64.6838) (24.1028, -0.75, 69.6143) (19.1723, -0.75, 88.0152) (37.5732, -0.75, 92.9457) (42.5037, -0.75, 74.5448) (65.525, -0.75, 27.82) (27.425, -0.75, 22.105) (65.525, -0.75, 8.77) (46.475, -0.75, 8.77) (27.425, -0.75, 3.055) (27.425, -0.75, -15.995) (46.475, -0.75, -10.28) (65.525, -0.75, -10.28) (65.525, -0.75, -29.33) (46.475, -0.75, -29.33) (27.425, -0.75, -35.045) (27.425, -0.75, -54.095) (27.425, -0.75, -73.145) (46.475, -0.75, -67.43) (65.525, -0.75, -67.43) (65.525, -0.75, -48.38) (46.475, -0.75, -48.38) (8.375, -0.75, -65.525) (8.375, -0.75, -46.475) (8.375, -0.75, -27.425) (8.375, -0.75, -8.375) (8.375, -0.75, 10.675) (8.375, -0.75, 29.725) (-10.675, -0.75, 39.25) (-29.725, -0.75, 39.25) (-48.775, -0.75, 39.25) (-29.725, -0.75, 20.2) (-10.675, -0.75, 20.2) (-10.675, -0.75, 1.15) (-29.725, -0.75, 1.15) (-29.725, -0.75, -17.9) (-10.675, -0.75, -17.9) (-10.675, -0.75, -36.95) (-10.675, -0.75, -56) (-29.725, -0.75, -36.95) (-29.725, -0.75, -56) (-48.775, -0.75, -36.95) (-65.525, -0.75, -20.2) (-46.475, -0.75, -20.2) (-65.525, -0.75, -39.25) (-27.425, -0.75, -39.25) (-10.675, -0.75, -39.25) (-29.725, -0.75, -20.2) (-29.725, -0.75, -1.15) (-65.525, -0.75, -1.15) (-65.525, -0.75, 17.9) (-65.525, -0.75, 36.95) (-65.525, -0.75, 56) (-46.475, -0.75, 56) (-48.775, -0.75, 56) (-29.725, -0.75, 56) (-29.725, -0.75, 36.95) (-10.675, -0.75, -20.2) (-10.675, -0.75, -1.15) (-27.425, -0.75, -1.15) (-27.425, -0.75, -20.2) (-10.675, -0.75, 17.9) (-10.675, -0.75, 36.95) (-10.675, -0.75, 56) (-27.425, -0.75, 36.95) (-27.425, -0.75, 56) (-27.425, -0.75, 17.9) (-8.375, -0.75, 46.475) (-8.375, -0.75, 27.425) (-8.375, -0.75, 8.375) (-8.375, -0.75, -10.675) (-8.375, -0.75, -29.725) (-8.375, -0.75, -48.775) (8.375, -0.75, -48.775) (8.375, -0.75, -29.725) (8.375, -0.75, -10.675) (8.375, -0.75, 8.375) (8.375, -0.75, 27.425) (8.375, -0.75, 46.475) (27.425, -0.75, 19.805) (46.475, -0.75, 25.52) (65.525, -0.75, 25.52) (65.525, -0.75, 6.47) (46.475, -0.75, 6.47) (27.425, -0.75, 0.755) (27.425, -0.75, -18.295) (46.475, -0.75, -12.58) (65.525, -0.75, -12.58) (65.525, -0.75, -31.63) (46.475, -0.75, -31.63) (27.425, -0.75, -37.345) (27.425, -0.75, -56.395) (46.475, -0.75, -50.68) (65.525, -0.75, -50.68) (48.775, -0.75, -50.68) (29.725, -0.75, -50.68) (10.675, -0.75, -56.395) (10.675, -0.75, -37.345) (29.725, -0.75, -31.63) (48.775, -0.75, -31.63) (48.775, -0.75, -12.58) (48.775, -0.75, 6.47) (29.725, -0.75, 6.47) (29.725, -0.75, -12.58) (10.675, -0.75, -18.295) (10.675, -0.75, 0.755) (48.775, -0.75, 25.52) (29.725, -0.75, 25.52) (10.675, -0.75, 19.805) (10.675, -0.75, 44.57) (65.525, -0.75, 44.57) (-29.725, -0.75, 17.9)